Autodesk Fusion 360 part; units mm, degrees
(part 9 of 9)
equation "d2606 = ( ( ( ( layoutGap + keycapSize / 2 + 2 * keyPitch ) - holderStemX ) + ( 2.5 mm ) - 0.5 mm ) + ( 1 mm ) ) - ( ( ( layoutGap + keycapSize / 2 + 2 * keyPitch ) - holderStemX ) + ( 2.5 mm ) - 0.5 mm )"
equation "d2607 = ( ( ( ( ( ( keyRowTwo ) - holderStemY ) - 1.2 mm ) * cos(caseTilt) + ( holderBottomDepth + holderLidGap ) * sin(caseTilt) ) - 1.5 mm ) + ( 3 mm ) ) - ( ( ( ( ( keyRowTwo ) - holderStemY ) - 1.2 mm ) * cos(caseTilt) + ( holderBottomDepth + holderLidGap ) * sin(caseTilt) ) - 1.5 mm )"
equation "d2608 = ( frontHeight + ( ( ( keyRowTwo ) - holderStemY ) - 1.2 mm ) * sin(caseTilt) - ( holderBottomDepth + holderLidGap ) * cos(caseTilt) ) - bottomThickness + 0.5 mm"
equation "d2610 = ( ( ( layoutGap + keycapSize / 2 + 2 * keyPitch ) - holderStemX ) + ( 2.5 mm ) - 0.5 mm ) - 0.1 mm"
equation "d2611 = ( ( ( ( keyRowTwo ) - holderStemY ) - 1.2 mm ) - 2 mm ) + faceOriginV"
equation "d2612 = ( ( ( ( ( layoutGap + keycapSize / 2 + 2 * keyPitch ) - holderStemX ) + ( 2.5 mm ) - 0.5 mm ) - 0.1 mm ) + ( 1.2 mm ) ) - ( ( ( ( layoutGap + keycapSize / 2 + 2 * keyPitch ) - holderStemX ) + ( 2.5 mm ) - 0.5 mm ) - 0.1 mm )"
equation "d2613 = ( ( ( ( ( ( keyRowTwo ) - holderStemY ) - 1.2 mm ) - 2 mm ) + faceOriginV ) + ( 4 mm ) ) - ( ( ( ( ( keyRowTwo ) - holderStemY ) - 1.2 mm ) - 2 mm ) + faceOriginV )"
equation "d2614 = rearHeight"
equation "d2616 = layoutGap + ( displayWidth - oledBoardWidth ) / 2 - oledFitClearance"
equation "d2617 = ( controlCenter - oledBoardLength / 2 - oledFitClearance ) + faceOriginV"
equation "d2618 = ( ( layoutGap + ( displayWidth - oledBoardWidth ) / 2 - oledFitClearance ) + ( oledBoardWidth + 2 * oledFitClearance ) ) - ( layoutGap + ( displayWidth - oledBoardWidth ) / 2 - oledFitClearance )"
equation "d2619 = ( ( ( controlCenter - oledBoardLength / 2 - oledFitClearance ) + faceOriginV ) + ( oledBoardLength + 2 * oledFitClearance ) ) - ( ( controlCenter - oledBoardLength / 2 - oledFitClearance ) + faceOriginV )"
equation "d2620 = -( oledBackDepth + oledFitClearance - shellWall - carrierClearance )"
equation "d2622 = ( 115 mm ) - 11 mm"
equation "d2623 = ( ( keyRowOne ) - 11 mm ) + faceOriginV"
equation "d2624 = ( ( ( 115 mm ) - 11 mm ) + ( 22 mm ) ) - ( ( 115 mm ) - 11 mm )"
equation "d2625 = ( ( ( ( keyRowOne ) - 11 mm ) + faceOriginV ) + ( 22 mm ) ) - ( ( ( keyRowOne ) - 11 mm ) + faceOriginV )"
equation "d2626 = -( carrierThickness )"
equation "d2628 = ( 115 mm ) - switchOpening / 2"
equation "d2629 = ( ( keyRowOne ) - switchOpening / 2 ) + faceOriginV"
equation "d2630 = ( ( ( 115 mm ) - switchOpening / 2 ) + ( switchOpening ) ) - ( ( 115 mm ) - switchOpening / 2 )"
equation "d2631 = ( ( ( ( keyRowOne ) - switchOpening / 2 ) + faceOriginV ) + ( switchOpening ) ) - ( ( ( keyRowOne ) - switchOpening / 2 ) + faceOriginV )"
equation "d2632 = -( carrierThickness + 0.1 mm )"
equation "d2634 = ( 115 mm ) - holderFrameX / 2"
equation "d2635 = ( ( keyRowOne ) - holderFrameY / 2 ) + faceOriginV"
equation "d2636 = ( ( ( 115 mm ) - holderFrameX / 2 ) + ( holderFrameX ) ) - ( ( 115 mm ) - holderFrameX / 2 )"
equation "d2637 = ( ( ( ( keyRowOne ) - holderFrameY / 2 ) + faceOriginV ) + ( holderFrameY ) ) - ( ( ( keyRowOne ) - holderFrameY / 2 ) + faceOriginV )"
equation "d2638 = -( holderBottomDepth + holderHookThickness - shellWall - carrierClearance - carrierThickness )"
equation "d2640 = ( 115 mm ) - holderSwitchVoid / 2"
equation "d2641 = ( ( keyRowOne ) - holderSwitchVoid / 2 ) + faceOriginV"
equation "d2642 = ( ( ( 115 mm ) - holderSwitchVoid / 2 ) + ( holderSwitchVoid ) ) - ( ( 115 mm ) - holderSwitchVoid / 2 )"
equation "d2643 = ( ( ( ( keyRowOne ) - holderSwitchVoid / 2 ) + faceOriginV ) + ( holderSwitchVoid ) ) - ( ( ( keyRowOne ) - holderSwitchVoid / 2 ) + faceOriginV )"
equation "d2644 = -( holderTopDepth - shellWall - carrierClearance - carrierThickness )"
equation "d2646 = ( ( 115 mm ) - holderStemX ) - holderWidth / 2 - holderFit"
equation "d2647 = ( ( ( keyRowOne ) - holderStemY ) - holderLength / 2 - holderFit ) + faceOriginV"
equation "d2648 = ( ( ( ( 115 mm ) - holderStemX ) - holderWidth / 2 - holderFit ) + ( holderWidth + 2 * holderFit ) ) - ( ( ( 115 mm ) - holderStemX ) - holderWidth / 2 - holderFit )"
equation "d2649 = ( ( ( ( ( keyRowOne ) - holderStemY ) - holderLength / 2 - holderFit ) + faceOriginV ) + ( holderLength + 2 * holderFit ) ) - ( ( ( ( keyRowOne ) - holderStemY ) - holderLength / 2 - holderFit ) + faceOriginV )"
equation "d2650 = -( holderHeight + holderHookThickness + 0.2 mm )"
equation "d2652 = ( ( 115 mm ) - holderStemX ) - holderFrameX / 2 - 0.1 mm"
equation "d2653 = ( ( ( ( keyRowOne ) - holderStemY ) + holderSpringY ) - holderSpringWidth / 2 - 0.6 mm ) + faceOriginV"
equation "d2654 = ( ( ( ( 115 mm ) - holderStemX ) - holderFrameX / 2 - 0.1 mm ) + ( holderFrameX / 2 - holderWidth / 2 - holderFit + 0.1 mm ) ) - ( ( ( 115 mm ) - holderStemX ) - holderFrameX / 2 - 0.1 mm )"
equation "d2655 = ( ( ( ( ( ( keyRowOne ) - holderStemY ) + holderSpringY ) - holderSpringWidth / 2 - 0.6 mm ) + faceOriginV ) + ( 0.6 mm ) ) - ( ( ( ( ( keyRowOne ) - holderStemY ) + holderSpringY ) - holderSpringWidth / 2 - 0.6 mm ) + faceOriginV )"
equation "d2656 = -( holderBottomDepth + holderHookThickness - shellWall - carrierClearance - carrierThickness - 1 mm + 0.2 mm )"
equation "d2658 = ( ( 115 mm ) - holderStemX ) - holderFrameX / 2 - 0.1 mm"
equation "d2659 = ( ( ( ( keyRowOne ) - holderStemY ) + holderSpringY ) + holderSpringWidth / 2 ) + faceOriginV"
equation "d2660 = ( ( ( ( 115 mm ) - holderStemX ) - holderFrameX / 2 - 0.1 mm ) + ( holderFrameX / 2 - holderWidth / 2 - holderFit + 0.1 mm ) ) - ( ( ( 115 mm ) - holderStemX ) - holderFrameX / 2 - 0.1 mm )"
equation "d2661 = ( ( ( ( ( ( keyRowOne ) - holderStemY ) + holderSpringY ) + holderSpringWidth / 2 ) + faceOriginV ) + ( 0.6 mm ) ) - ( ( ( ( ( keyRowOne ) - holderStemY ) + holderSpringY ) + holderSpringWidth / 2 ) + faceOriginV )"
equation "d2662 = -( holderBottomDepth + holderHookThickness - shellWall - carrierClearance - carrierThickness - 1 mm + 0.2 mm )"
equation "d2664 = ( ( 115 mm ) - holderStemX ) - holderFrameX / 2 + 0.8 mm"
equation "d2665 = ( ( ( ( keyRowOne ) - holderStemY ) + holderSpringY ) - holderSpringWidth / 2 ) + faceOriginV"
equation "d2666 = ( ( ( ( 115 mm ) - holderStemX ) - holderFrameX / 2 + 0.8 mm ) + ( holderFrameX / 2 - 0.8 mm - holderWidth / 2 - holderFit ) ) - ( ( ( 115 mm ) - holderStemX ) - holderFrameX / 2 + 0.8 mm )"
equation "d2667 = ( ( ( ( ( ( keyRowOne ) - holderStemY ) + holderSpringY ) - holderSpringWidth / 2 ) + faceOriginV ) + ( holderSpringWidth ) ) - ( ( ( ( ( keyRowOne ) - holderStemY ) + holderSpringY ) - holderSpringWidth / 2 ) + faceOriginV )"
equation "d2668 = -( holderHeight + holderHookThickness + 0.2 mm )"
equation "d2670 = ( ( 115 mm ) - holderStemX ) - holderFrameX / 2"
equation "d2671 = ( ( ( ( keyRowOne ) - holderStemY ) + holderSpringY ) - holderSpringWidth / 2 ) + faceOriginV"
equation "d2672 = ( ( ( ( 115 mm ) - holderStemX ) - holderFrameX / 2 ) + ( holderFrameX / 2 - holderWidth / 2 + holderHookOverlap ) ) - ( ( ( 115 mm ) - holderStemX ) - holderFrameX / 2 )"
equation "d2673 = ( ( ( ( ( ( keyRowOne ) - holderStemY ) + holderSpringY ) - holderSpringWidth / 2 ) + faceOriginV ) + ( holderSpringWidth ) ) - ( ( ( ( ( keyRowOne ) - holderStemY ) + holderSpringY ) - holderSpringWidth / 2 ) + faceOriginV )"
equation "d2674 = -( holderHookThickness )"
equation "d2677 = ( ( 115 mm ) - holderStemX ) + holderWidth / 2 + holderFit"
equation "d2678 = ( ( ( ( keyRowOne ) - holderStemY ) + holderSpringY ) - holderSpringWidth / 2 - 0.6 mm ) + faceOriginV"
equation "d2679 = ( ( ( ( 115 mm ) - holderStemX ) + holderWidth / 2 + holderFit ) + ( holderFrameX / 2 - holderWidth / 2 - holderFit + 0.1 mm ) ) - ( ( ( 115 mm ) - holderStemX ) + holderWidth / 2 + holderFit )"
equation "d2680 = ( ( ( ( ( ( keyRowOne ) - holderStemY ) + holderSpringY ) - holderSpringWidth / 2 - 0.6 mm ) + faceOriginV ) + ( 0.6 mm ) ) - ( ( ( ( ( keyRowOne ) - holderStemY ) + holderSpringY ) - holderSpringWidth / 2 - 0.6 mm ) + faceOriginV )"
equation "d2681 = -( holderBottomDepth + holderHookThickness - shellWall - carrierClearance - carrierThickness - 1 mm + 0.2 mm )"
equation "d2683 = ( ( 115 mm ) - holderStemX ) + holderWidth / 2 + holderFit"
equation "d2684 = ( ( ( ( keyRowOne ) - holderStemY ) + holderSpringY ) + holderSpringWidth / 2 ) + faceOriginV"
equation "d2685 = ( ( ( ( 115 mm ) - holderStemX ) + holderWidth / 2 + holderFit ) + ( holderFrameX / 2 - holderWidth / 2 - holderFit + 0.1 mm ) ) - ( ( ( 115 mm ) - holderStemX ) + holderWidth / 2 + holderFit )"
equation "d2686 = ( ( ( ( ( ( keyRowOne ) - holderStemY ) + holderSpringY ) + holderSpringWidth / 2 ) + faceOriginV ) + ( 0.6 mm ) ) - ( ( ( ( ( keyRowOne ) - holderStemY ) + holderSpringY ) + holderSpringWidth / 2 ) + faceOriginV )"
equation "d2687 = -( holderBottomDepth + holderHookThickness - shellWall - carrierClearance - carrierThickness - 1 mm + 0.2 mm )"
equation "d2689 = ( ( 115 mm ) - holderStemX ) + holderWidth / 2 + holderFit"
equation "d2690 = ( ( ( ( keyRowOne ) - holderStemY ) + holderSpringY ) - holderSpringWidth / 2 ) + faceOriginV"
equation "d2691 = ( ( ( ( 115 mm ) - holderStemX ) + holderWidth / 2 + holderFit ) + ( holderFrameX / 2 - 0.8 mm - holderWidth / 2 - holderFit ) ) - ( ( ( 115 mm ) - holderStemX ) + holderWidth / 2 + holderFit )"
equation "d2692 = ( ( ( ( ( ( keyRowOne ) - holderStemY ) + holderSpringY ) - holderSpringWidth / 2 ) + faceOriginV ) + ( holderSpringWidth ) ) - ( ( ( ( ( keyRowOne ) - holderStemY ) + holderSpringY ) - holderSpringWidth / 2 ) + faceOriginV )"
equation "d2693 = -( holderHeight + holderHookThickness + 0.2 mm )"
equation "d2695 = ( ( 115 mm ) - holderStemX ) + holderWidth / 2 - holderHookOverlap"
equation "d2696 = ( ( ( ( keyRowOne ) - holderStemY ) + holderSpringY ) - holderSpringWidth / 2 ) + faceOriginV"
equation "d2697 = ( ( ( ( 115 mm ) - holderStemX ) + holderWidth / 2 - holderHookOverlap ) + ( holderFrameX / 2 - holderWidth / 2 + holderHookOverlap ) ) - ( ( ( 115 mm ) - holderStemX ) + holderWidth / 2 - holderHookOverlap )"
equation "d2698 = ( ( ( ( ( ( keyRowOne ) - holderStemY ) + holderSpringY ) - holderSpringWidth / 2 ) + faceOriginV ) + ( holderSpringWidth ) ) - ( ( ( ( ( keyRowOne ) - holderStemY ) + holderSpringY ) - holderSpringWidth / 2 ) + faceOriginV )"
equation "d2699 = -( holderHookThickness )"
equation "d2702 = ( ( 115 mm ) - holderStemX ) + ( -3 mm ) - 0.5 mm"
equation "d2703 = ( ( ( keyRowOne ) - holderStemY ) + 4 mm ) + faceOriginV"
equation "d2704 = ( ( ( ( 115 mm ) - holderStemX ) + ( -3 mm ) - 0.5 mm ) + ( 1 mm ) ) - ( ( ( 115 mm ) - holderStemX ) + ( -3 mm ) - 0.5 mm )"
equation "d2705 = ( ( ( ( ( keyRowOne ) - holderStemY ) + 4 mm ) + faceOriginV ) + ( holderFrameY / 2 - 4 mm ) ) - ( ( ( ( keyRowOne ) - holderStemY ) + 4 mm ) + faceOriginV )"
equation "d2708 = ( ( 115 mm ) - holderStemX ) + ( 3 mm ) - 0.5 mm"
equation "d2709 = ( ( ( keyRowOne ) - holderStemY ) + 4 mm ) + faceOriginV"
equation "d2710 = ( ( ( ( 115 mm ) - holderStemX ) + ( 3 mm ) - 0.5 mm ) + ( 1 mm ) ) - ( ( ( 115 mm ) - holderStemX ) + ( 3 mm ) - 0.5 mm )"
equation "d2711 = ( ( ( ( ( keyRowOne ) - holderStemY ) + 4 mm ) + faceOriginV ) + ( holderFrameY / 2 - 4 mm ) ) - ( ( ( ( keyRowOne ) - holderStemY ) + 4 mm ) + faceOriginV )"
equation "d2714 = ( ( 115 mm ) - holderStemX ) - holderFrameX / 2 - 0.1 mm"
equation "d2715 = ( ( ( keyRowOne ) - holderStemY ) - 5.1 mm ) + faceOriginV"
equation "d2716 = ( ( ( ( 115 mm ) - holderStemX ) - holderFrameX / 2 - 0.1 mm ) + ( holderFrameX / 2 - holderWidth / 2 + 0.1 mm ) ) - ( ( ( 115 mm ) - holderStemX ) - holderFrameX / 2 - 0.1 mm )"
equation "d2717 = ( ( ( ( ( keyRowOne ) - holderStemY ) - 5.1 mm ) + faceOriginV ) + ( 7.8 mm ) ) - ( ( ( ( keyRowOne ) - holderStemY ) - 5.1 mm ) + faceOriginV )"
equation "d2718 = -( holderHeight + holderHookThickness - 1.2 mm + 0.2 mm )"
equation "d2720 = ( ( 115 mm ) - holderStemX ) + holderWidth / 2"
equation "d2721 = ( ( ( keyRowOne ) - holderStemY ) - 5.1 mm ) + faceOriginV"
equation "d2722 = ( ( ( ( 115 mm ) - holderStemX ) + holderWidth / 2 ) + ( holderFrameX / 2 - holderWidth / 2 + 0.1 mm ) ) - ( ( ( 115 mm ) - holderStemX ) + holderWidth / 2 )"
equation "d2723 = ( ( ( ( ( keyRowOne ) - holderStemY ) - 5.1 mm ) + faceOriginV ) + ( 7.8 mm ) ) - ( ( ( ( keyRowOne ) - holderStemY ) - 5.1 mm ) + faceOriginV )"
equation "d2724 = -( holderHeight + holderHookThickness - 1.2 mm + 0.2 mm )"
equation "d2726 = ( 115 mm ) - 11 mm"
equation "d2727 = ( ( keyRowOne ) * cos(caseTilt) + ( holderBottomDepth + holderLidGap ) * sin(caseTilt) ) - 11 mm"
equation "d2728 = ( ( ( 115 mm ) - 11 mm ) + ( 22 mm ) ) - ( ( 115 mm ) - 11 mm )"
equation "d2729 = ( ( ( ( keyRowOne ) * cos(caseTilt) + ( holderBottomDepth + holderLidGap ) * sin(caseTilt) ) - 11 mm ) + ( 22 mm ) ) - ( ( ( keyRowOne ) * cos(caseTilt) + ( holderBottomDepth + holderLidGap ) * sin(caseTilt) ) - 11 mm )"
equation "d2730 = bottomThickness"
equation "d2732 = ( ( 115 mm ) - holderStemX ) + ( -2.5 mm ) - 1.2 mm"
equation "d2733 = ( ( ( ( keyRowOne ) - holderStemY ) - 1.2 mm ) * cos(caseTilt) + ( holderBottomDepth + holderLidGap ) * sin(caseTilt) ) - 2.5 mm"
equation "d2734 = ( ( ( ( 115 mm ) - holderStemX ) + ( -2.5 mm ) - 1.2 mm ) + ( 2.4 mm ) ) - ( ( ( 115 mm ) - holderStemX ) + ( -2.5 mm ) - 1.2 mm )"
equation "d2735 = ( ( ( ( ( ( keyRowOne ) - holderStemY ) - 1.2 mm ) * cos(caseTilt) + ( holderBottomDepth + holderLidGap ) * sin(caseTilt) ) - 2.5 mm ) + ( 5 mm ) ) - ( ( ( ( ( keyRowOne ) - holderStemY ) - 1.2 mm ) * cos(caseTilt) + ( holderBottomDepth + holderLidGap ) * sin(caseTilt) ) - 2.5 mm )"
equation "d2736 = ( frontHeight + ( ( ( keyRowOne ) - holderStemY ) - 1.2 mm ) * sin(caseTilt) - ( holderBottomDepth + holderLidGap ) * cos(caseTilt) ) - bottomThickness - 2 mm"
equation "d2738 = ( ( 115 mm ) - holderStemX ) + ( -2.5 mm ) - 0.5 mm"
equation "d2739 = ( ( ( ( keyRowOne ) - holderStemY ) - 1.2 mm ) * cos(caseTilt) + ( holderBottomDepth + holderLidGap ) * sin(caseTilt) ) - 1.5 mm"
equation "d2740 = ( ( ( ( 115 mm ) - holderStemX ) + ( -2.5 mm ) - 0.5 mm ) + ( 1 mm ) ) - ( ( ( 115 mm ) - holderStemX ) + ( -2.5 mm ) - 0.5 mm )"
equation "d2741 = ( ( ( ( ( ( keyRowOne ) - holderStemY ) - 1.2 mm ) * cos(caseTilt) + ( holderBottomDepth + holderLidGap ) * sin(caseTilt) ) - 1.5 mm ) + ( 3 mm ) ) - ( ( ( ( ( keyRowOne ) - holderStemY ) - 1.2 mm ) * cos(caseTilt) + ( holderBottomDepth + holderLidGap ) * sin(caseTilt) ) - 1.5 mm )"
equation "d2742 = ( frontHeight + ( ( ( keyRowOne ) - holderStemY ) - 1.2 mm ) * sin(caseTilt) - ( holderBottomDepth + holderLidGap ) * cos(caseTilt) ) - bottomThickness + 0.5 mm"
equation "d2744 = ( ( ( 115 mm ) - holderStemX ) + ( -2.5 mm ) - 0.5 mm ) - 0.1 mm"
equation "d2745 = ( ( ( ( keyRowOne ) - holderStemY ) - 1.2 mm ) - 2 mm ) + faceOriginV"
equation "d2746 = ( ( ( ( ( 115 mm ) - holderStemX ) + ( -2.5 mm ) - 0.5 mm ) - 0.1 mm ) + ( 1.2 mm ) ) - ( ( ( ( 115 mm ) - holderStemX ) + ( -2.5 mm ) - 0.5 mm ) - 0.1 mm )"
equation "d2747 = ( ( ( ( ( ( keyRowOne ) - holderStemY ) - 1.2 mm ) - 2 mm ) + faceOriginV ) + ( 4 mm ) ) - ( ( ( ( ( keyRowOne ) - holderStemY ) - 1.2 mm ) - 2 mm ) + faceOriginV )"
equation "d2748 = rearHeight"
equation "d2750 = ( ( 115 mm ) - holderStemX ) + ( 2.5 mm ) - 1.2 mm"
equation "d2751 = ( ( ( ( keyRowOne ) - holderStemY ) - 1.2 mm ) * cos(caseTilt) + ( holderBottomDepth + holderLidGap ) * sin(caseTilt) ) - 2.5 mm"
equation "d2752 = ( ( ( ( 115 mm ) - holderStemX ) + ( 2.5 mm ) - 1.2 mm ) + ( 2.4 mm ) ) - ( ( ( 115 mm ) - holderStemX ) + ( 2.5 mm ) - 1.2 mm )"
equation "d2753 = ( ( ( ( ( ( keyRowOne ) - holderStemY ) - 1.2 mm ) * cos(caseTilt) + ( holderBottomDepth + holderLidGap ) * sin(caseTilt) ) - 2.5 mm ) + ( 5 mm ) ) - ( ( ( ( ( keyRowOne ) - holderStemY ) - 1.2 mm ) * cos(caseTilt) + ( holderBottomDepth + holderLidGap ) * sin(caseTilt) ) - 2.5 mm )"
equation "d2754 = ( frontHeight + ( ( ( keyRowOne ) - holderStemY ) - 1.2 mm ) * sin(caseTilt) - ( holderBottomDepth + holderLidGap ) * cos(caseTilt) ) - bottomThickness - 2 mm"
equation "d2756 = ( ( 115 mm ) - holderStemX ) + ( 2.5 mm ) - 0.5 mm"
equation "d2757 = ( ( ( ( keyRowOne ) - holderStemY ) - 1.2 mm ) * cos(caseTilt) + ( holderBottomDepth + holderLidGap ) * sin(caseTilt) ) - 1.5 mm"
equation "d2758 = ( ( ( ( 115 mm ) - holderStemX ) + ( 2.5 mm ) - 0.5 mm ) + ( 1 mm ) ) - ( ( ( 115 mm ) - holderStemX ) + ( 2.5 mm ) - 0.5 mm )"
equation "d2759 = ( ( ( ( ( ( keyRowOne ) - holderStemY ) - 1.2 mm ) * cos(caseTilt) + ( holderBottomDepth + holderLidGap ) * sin(caseTilt) ) - 1.5 mm ) + ( 3 mm ) ) - ( ( ( ( ( keyRowOne ) - holderStemY ) - 1.2 mm ) * cos(caseTilt) + ( holderBottomDepth + holderLidGap ) * sin(caseTilt) ) - 1.5 mm )"
equation "d2760 = ( frontHeight + ( ( ( keyRowOne ) - holderStemY ) - 1.2 mm ) * sin(caseTilt) - ( holderBottomDepth + holderLidGap ) * cos(caseTilt) ) - bottomThickness + 0.5 mm"
equation "d2762 = ( ( ( 115 mm ) - holderStemX ) + ( 2.5 mm ) - 0.5 mm ) - 0.1 mm"
equation "d2763 = ( ( ( ( keyRowOne ) - holderStemY ) - 1.2 mm ) - 2 mm ) + faceOriginV"
equation "d2764 = ( ( ( ( ( 115 mm ) - holderStemX ) + ( 2.5 mm ) - 0.5 mm ) - 0.1 mm ) + ( 1.2 mm ) ) - ( ( ( ( 115 mm ) - holderStemX ) + ( 2.5 mm ) - 0.5 mm ) - 0.1 mm )"
equation "d2765 = ( ( ( ( ( ( keyRowOne ) - holderStemY ) - 1.2 mm ) - 2 mm ) + faceOriginV ) + ( 4 mm ) ) - ( ( ( ( ( keyRowOne ) - holderStemY ) - 1.2 mm ) - 2 mm ) + faceOriginV )"
equation "d2766 = rearHeight"
equation "compactTrialX = 145 mm" comment "Separate V2 coupon center"
equation "compactGuideClearance = 0.2 mm" comment "Radial clearance in STL 0.95 mm side notches"
equation "compactGuideHeight = 3 mm" comment "Guide within 3.2 mm notched region"
equation "compactStopWidth = 1.8 mm" comment "Wider upper stops for physical test"
equation "compactWireDiameter = 1.5 mm" comment "Provisional through-wall wire routing diameter"
equation "d2773 = compactTrialX - 11 mm"
equation "d2774 = ( keyRowOne - 11 mm ) + faceOriginV"
equation "d2775 = ( ( compactTrialX - 11 mm ) + ( 22 mm ) ) - ( compactTrialX - 11 mm )"
equation "d2776 = ( ( ( keyRowOne - 11 mm ) + faceOriginV ) + ( 22 mm ) ) - ( ( keyRowOne - 11 mm ) + faceOriginV )"
equation "d2777 = -( carrierThickness )"
equation "d2779 = compactTrialX - switchOpening / 2"
equation "d2780 = ( keyRowOne - switchOpening / 2 ) + faceOriginV"
equation "d2781 = ( ( compactTrialX - switchOpening / 2 ) + ( switchOpening ) ) - ( compactTrialX - switchOpening / 2 )"
equation "d2782 = ( ( ( keyRowOne - switchOpening / 2 ) + faceOriginV ) + ( switchOpening ) ) - ( ( keyRowOne - switchOpening / 2 ) + faceOriginV )"
equation "d2783 = -( carrierThickness + 0.1 mm )"
equation "d2785 = compactTrialX - holderFrameX / 2"
equation "d2786 = ( keyRowOne - holderFrameY / 2 ) + faceOriginV"
equation "d2787 = ( ( compactTrialX - holderFrameX / 2 ) + ( holderFrameX ) ) - ( compactTrialX - holderFrameX / 2 )"
equation "d2788 = ( ( ( keyRowOne - holderFrameY / 2 ) + faceOriginV ) + ( holderFrameY ) ) - ( ( keyRowOne - holderFrameY / 2 ) + faceOriginV )"
equation "d2789 = -( holderBottomDepth - shellWall - carrierClearance - carrierThickness )"
equation "d2791 = compactTrialX - holderSwitchVoid / 2"
equation "d2792 = ( keyRowOne - holderSwitchVoid / 2 ) + faceOriginV"
equation "d2793 = ( ( compactTrialX - holderSwitchVoid / 2 ) + ( holderSwitchVoid ) ) - ( compactTrialX - holderSwitchVoid / 2 )"
equation "d2794 = ( ( ( keyRowOne - holderSwitchVoid / 2 ) + faceOriginV ) + ( holderSwitchVoid ) ) - ( ( keyRowOne - holderSwitchVoid / 2 ) + faceOriginV )"
equation "d2795 = -( holderTopDepth - shellWall - carrierClearance - carrierThickness )"
equation "d2797 = compactTrialX - 5.42601681 mm - holderFit"
equation "d2798 = ( keyRowOne - 6.37220383 mm - holderFit ) + faceOriginV"
equation "d2799 = ( ( compactTrialX - 5.42601681 mm - holderFit ) + ( 11.03147984 mm + 2 * holderFit ) ) - ( compactTrialX - 5.42601681 mm - holderFit )"
equation "d2800 = ( ( ( keyRowOne - 6.37220383 mm - holderFit ) + faceOriginV ) + ( 9.74910235 mm + 2 * holderFit ) ) - ( ( keyRowOne - 6.37220383 mm - holderFit ) + faceOriginV )"
equation "d2801 = -( holderHeight + 0.1 mm )"
equation "d2803 = compactTrialX + ( -1 * 3 mm ) - compactStopWidth / 2"
equation "d2804 = ( keyRowOne + 2.6 mm ) + faceOriginV"
equation "d2805 = ( ( compactTrialX + ( -1 * 3 mm ) - compactStopWidth / 2 ) + ( compactStopWidth ) ) - ( compactTrialX + ( -1 * 3 mm ) - compactStopWidth / 2 )"
equation "d2806 = ( ( ( keyRowOne + 2.6 mm ) + faceOriginV ) + ( holderFrameY / 2 - 2.6 mm ) ) - ( ( keyRowOne + 2.6 mm ) + faceOriginV )"
equation "d2809 = compactTrialX - holderFrameX / 2"
equation "d2810 = ( keyRowOne - 0.35 mm ) + faceOriginV"
equation "d2811 = ( ( compactTrialX - holderFrameX / 2 ) + ( holderFrameX / 2 - 4.8 mm ) ) - ( compactTrialX - holderFrameX / 2 )"
equation "d2812 = ( ( ( keyRowOne - 0.35 mm ) + faceOriginV ) + ( 0.7 mm ) ) - ( ( keyRowOne - 0.35 mm ) + faceOriginV )"
equation "d2813 = compactGuideHeight"
equation "d2815 = compactTrialX + ( -1 * 4.8 mm )"
equation "d2816 = ( keyRowOne ) + faceOriginV"
equation "d2817 = 2 * ( 0.95 mm - compactGuideClearance )"
equation "d2818 = compactGuideHeight"
equation "d2820 = compactTrialX + ( 1 * 3 mm ) - compactStopWidth / 2"
equation "d2821 = ( keyRowOne + 2.6 mm ) + faceOriginV"
equation "d2822 = ( ( compactTrialX + ( 1 * 3 mm ) - compactStopWidth / 2 ) + ( compactStopWidth ) ) - ( compactTrialX + ( 1 * 3 mm ) - compactStopWidth / 2 )"
equation "d2823 = ( ( ( keyRowOne + 2.6 mm ) + faceOriginV ) + ( holderFrameY / 2 - 2.6 mm ) ) - ( ( keyRowOne + 2.6 mm ) + faceOriginV )"
equation "d2826 = compactTrialX + 4.8 mm"
equation "d2827 = ( keyRowOne - 0.35 mm ) + faceOriginV"
equation "d2828 = ( ( compactTrialX + 4.8 mm ) + ( holderFrameX / 2 - 4.8 mm ) ) - ( compactTrialX + 4.8 mm )"
equation "d2829 = ( ( ( keyRowOne - 0.35 mm ) + faceOriginV ) + ( 0.7 mm ) ) - ( ( keyRowOne - 0.35 mm ) + faceOriginV )"
equation "d2830 = compactGuideHeight"
equation "d2832 = compactTrialX + ( 1 * 4.8 mm )"
equation "d2833 = ( keyRowOne ) + faceOriginV"
equation "d2834 = 2 * ( 0.95 mm - compactGuideClearance )"
equation "d2835 = compactGuideHeight"
equation "d2837 = compactTrialX - 10 mm"
equation "d2839 = -( -1.7062782001271268 cm )"
equation "d2841 = compactWireDiameter"
equation "d2844 = -( -1.68700663682872 cm )"
equation "d2846 = compactWireDiameter"
equation "d2849 = -( -1.9961218786424535 cm )"
equation "d2851 = compactWireDiameter"
equation "d2854 = caseTilt"
equation "d2856 = 1 * ( keyRowOne + 10 mm + frontHeight * sin(caseTilt) )"
equation "d2859 = -( -1.7982695244660625 cm )"
equation "d2860 = compactWireDiameter"
equation "d2861 = -( 20 mm )"
equation "compactV3TrialX = 175 mm" comment "Separate V3 coupon center"
equation "compactV3Shift = 3 mm" comment "Move holder toward switch based on pin-tip measurement"
equation "compactV3TopDepth = holderTopDepth - compactV3Shift" comment "Local trial depth; preserve main carrier"
equation "compactV3BottomDepth = compactV3TopDepth + holderHeight" comment "New holder bottom datum"
equation "compactV3GuideClearance = 0.2 mm" comment "Radial clearance in STL 0.95 mm side notches"
equation "compactV3GuideHeight = 3 mm" comment "Guide within 3.2 mm notched region"
equation "compactV3StopWidth = 1.8 mm" comment "Wider upper stops for physical test"
equation "compactV3WireDiameter = 1.5 mm" comment "Provisional through-wall wire routing diameter"
equation "d2871 = -compactV3TopDepth"
equation "d2873 = -compactV3BottomDepth"
equation "d2875 = compactV3TrialX - 11 mm"
equation "d2876 = ( keyRowOne - 11 mm ) + faceOriginV"
equation "d2877 = ( ( compactV3TrialX - 11 mm ) + ( 22 mm ) ) - ( compactV3TrialX - 11 mm )"
equation "d2878 = ( ( ( keyRowOne - 11 mm ) + faceOriginV ) + ( 22 mm ) ) - ( ( keyRowOne - 11 mm ) + faceOriginV )"
equation "d2879 = -( carrierThickness )"
equation "d2881 = compactV3TrialX - switchOpening / 2"
equation "d2882 = ( keyRowOne - switchOpening / 2 ) + faceOriginV"
equation "d2883 = ( ( compactV3TrialX - switchOpening / 2 ) + ( switchOpening ) ) - ( compactV3TrialX - switchOpening / 2 )"
equation "d2884 = ( ( ( keyRowOne - switchOpening / 2 ) + faceOriginV ) + ( switchOpening ) ) - ( ( keyRowOne - switchOpening / 2 ) + faceOriginV )"
equation "d2885 = -( carrierThickness + 0.1 mm )"
equation "d2887 = compactV3TrialX - holderFrameX / 2"
equation "d2888 = ( keyRowOne - holderFrameY / 2 ) + faceOriginV"
equation "d2889 = ( ( compactV3TrialX - holderFrameX / 2 ) + ( holderFrameX ) ) - ( compactV3TrialX - holderFrameX / 2 )"
equation "d2890 = ( ( ( keyRowOne - holderFrameY / 2 ) + faceOriginV ) + ( holderFrameY ) ) - ( ( keyRowOne - holderFrameY / 2 ) + faceOriginV )"
equation "d2891 = -( compactV3BottomDepth - shellWall - carrierClearance - carrierThickness )"
equation "d2893 = compactV3TrialX - holderSwitchVoid / 2"
equation "d2894 = ( keyRowOne - holderSwitchVoid / 2 ) + faceOriginV"
equation "d2895 = ( ( compactV3TrialX - holderSwitchVoid / 2 ) + ( holderSwitchVoid ) ) - ( compactV3TrialX - holderSwitchVoid / 2 )"
equation "d2896 = ( ( ( keyRowOne - holderSwitchVoid / 2 ) + faceOriginV ) + ( holderSwitchVoid ) ) - ( ( keyRowOne - holderSwitchVoid / 2 ) + faceOriginV )"
equation "d2897 = -( compactV3TopDepth - shellWall - carrierClearance - carrierThickness )"
equation "d2899 = compactV3TrialX - 5.42601681 mm - holderFit"
equation "d2900 = ( keyRowOne - 6.37220383 mm - holderFit ) + faceOriginV"
equation "d2901 = ( ( compactV3TrialX - 5.42601681 mm - holderFit ) + ( 11.03147984 mm + 2 * holderFit ) ) - ( compactV3TrialX - 5.42601681 mm - holderFit )"
equation "d2902 = ( ( ( keyRowOne - 6.37220383 mm - holderFit ) + faceOriginV ) + ( 9.74910235 mm + 2 * holderFit ) ) - ( ( keyRowOne - 6.37220383 mm - holderFit ) + faceOriginV )"
equation "d2903 = -( holderHeight + 0.1 mm )"
equation "d2905 = compactV3TrialX + ( -1 * 3 mm ) - compactV3StopWidth / 2"
equation "d2906 = ( keyRowOne + 2.6 mm ) + faceOriginV"
equation "d2907 = ( ( compactV3TrialX + ( -1 * 3 mm ) - compactV3StopWidth / 2 ) + ( compactV3StopWidth ) ) - ( compactV3TrialX + ( -1 * 3 mm ) - compactV3StopWidth / 2 )"
equation "d2908 = ( ( ( keyRowOne + 2.6 mm ) + faceOriginV ) + ( holderFrameY / 2 - 2.6 mm ) ) - ( ( keyRowOne + 2.6 mm ) + faceOriginV )"
equation "d2911 = compactV3TrialX - holderFrameX / 2"
equation "d2912 = ( keyRowOne - 0.35 mm ) + faceOriginV"
equation "d2913 = ( ( compactV3TrialX - holderFrameX / 2 ) + ( holderFrameX / 2 - 4.8 mm ) ) - ( compactV3TrialX - holderFrameX / 2 )"
equation "d2914 = ( ( ( keyRowOne - 0.35 mm ) + faceOriginV ) + ( 0.7 mm ) ) - ( ( keyRowOne - 0.35 mm ) + faceOriginV )"
equation "d2915 = compactV3GuideHeight"
equation "d2917 = compactV3TrialX + ( -1 * 4.8 mm )"
equation "d2918 = ( keyRowOne ) + faceOriginV"
equation "d2919 = 2 * ( 0.95 mm - compactV3GuideClearance )"
equation "d2920 = compactV3GuideHeight"
equation "d2922 = compactV3TrialX + ( 1 * 3 mm ) - compactV3StopWidth / 2"
equation "d2923 = ( keyRowOne + 2.6 mm ) + faceOriginV"
equation "d2924 = ( ( compactV3TrialX + ( 1 * 3 mm ) - compactV3StopWidth / 2 ) + ( compactV3StopWidth ) ) - ( compactV3TrialX + ( 1 * 3 mm ) - compactV3StopWidth / 2 )"
equation "d2925 = ( ( ( keyRowOne + 2.6 mm ) + faceOriginV ) + ( holderFrameY / 2 - 2.6 mm ) ) - ( ( keyRowOne + 2.6 mm ) + faceOriginV )"
equation "d2928 = compactV3TrialX + 4.8 mm"
equation "d2929 = ( keyRowOne - 0.35 mm ) + faceOriginV"
equation "d2930 = ( ( compactV3TrialX + 4.8 mm ) + ( holderFrameX / 2 - 4.8 mm ) ) - ( compactV3TrialX + 4.8 mm )"
equation "d2931 = ( ( ( keyRowOne - 0.35 mm ) + faceOriginV ) + ( 0.7 mm ) ) - ( ( keyRowOne - 0.35 mm ) + faceOriginV )"
equation "d2932 = compactV3GuideHeight"
equation "d2934 = compactV3TrialX + ( 1 * 4.8 mm )"
equation "d2935 = ( keyRowOne ) + faceOriginV"
equation "d2936 = 2 * ( 0.95 mm - compactV3GuideClearance )"
equation "d2937 = compactV3GuideHeight"
equation "d2939 = compactV3TrialX - 10 mm"
equation "d2941 = -( -2.0051366095546506 cm )"
equation "d2943 = compactV3WireDiameter"
equation "d2946 = -( -1.9858650462562437 cm )"
equation "d2948 = compactV3WireDiameter"
equation "d2951 = -( -2.294980288069977 cm )"
equation "d2953 = compactV3WireDiameter"
equation "d2956 = caseTilt"
equation "d2958 = 1 * ( keyRowOne + 10 mm + frontHeight * sin(caseTilt) )"
equation "d2961 = -( -2.098269524466062 cm )"
equation "d2962 = compactV3WireDiameter"
equation "d2963 = -( 20 mm )"
equation "d2965 = -( compactV3BottomDepth + holderLidGap )"
equation "d2967 = compactV3TrialX - 11 mm"
equation "d2968 = ( ( keyRowOne ) * cos(caseTilt) + ( compactV3BottomDepth + holderLidGap ) * sin(caseTilt) ) - 11 mm"
equation "d2969 = ( ( compactV3TrialX - 11 mm ) + ( 22 mm ) ) - ( compactV3TrialX - 11 mm )"
equation "d2970 = ( ( ( ( keyRowOne ) * cos(caseTilt) + ( compactV3BottomDepth + holderLidGap ) * sin(caseTilt) ) - 11 mm ) + ( 22 mm ) ) - ( ( ( keyRowOne ) * cos(caseTilt) + ( compactV3BottomDepth + holderLidGap ) * sin(caseTilt) ) - 11 mm )"
equation "d2971 = bottomThickness"
equation "d2973 = ( ( compactV3TrialX ) - holderStemX ) + ( -2.5 mm ) - 1.2 mm"
equation "d2974 = ( ( ( ( keyRowOne ) - holderStemY ) - 1.2 mm ) * cos(caseTilt) + ( compactV3BottomDepth + holderLidGap ) * sin(caseTilt) ) - 2.5 mm"
equation "d2975 = ( ( ( ( compactV3TrialX ) - holderStemX ) + ( -2.5 mm ) - 1.2 mm ) + ( 2.4 mm ) ) - ( ( ( compactV3TrialX ) - holderStemX ) + ( -2.5 mm ) - 1.2 mm )"
equation "d2976 = ( ( ( ( ( ( keyRowOne ) - holderStemY ) - 1.2 mm ) * cos(caseTilt) + ( compactV3BottomDepth + holderLidGap ) * sin(caseTilt) ) - 2.5 mm ) + ( 5 mm ) ) - ( ( ( ( ( keyRowOne ) - holderStemY ) - 1.2 mm ) * cos(caseTilt) + ( compactV3BottomDepth + holderLidGap ) * sin(caseTilt) ) - 2.5 mm )"
equation "d2977 = ( frontHeight + ( ( ( keyRowOne ) - holderStemY ) - 1.2 mm ) * sin(caseTilt) - ( compactV3BottomDepth + holderLidGap ) * cos(caseTilt) ) - bottomThickness - 2 mm"
equation "d2979 = ( ( compactV3TrialX ) - holderStemX ) + ( -2.5 mm ) - 0.5 mm"
equation "d2980 = ( ( ( ( keyRowOne ) - holderStemY ) - 1.2 mm ) * cos(caseTilt) + ( compactV3BottomDepth + holderLidGap ) * sin(caseTilt) ) - 1.5 mm"
equation "d2981 = ( ( ( ( compactV3TrialX ) - holderStemX ) + ( -2.5 mm ) - 0.5 mm ) + ( 1 mm ) ) - ( ( ( compactV3TrialX ) - holderStemX ) + ( -2.5 mm ) - 0.5 mm )"
equation "d2982 = ( ( ( ( ( ( keyRowOne ) - holderStemY ) - 1.2 mm ) * cos(caseTilt) + ( compactV3BottomDepth + holderLidGap ) * sin(caseTilt) ) - 1.5 mm ) + ( 3 mm ) ) - ( ( ( ( ( keyRowOne ) - holderStemY ) - 1.2 mm ) * cos(caseTilt) + ( compactV3BottomDepth + holderLidGap ) * sin(caseTilt) ) - 1.5 mm )"
equation "d2983 = ( frontHeight + ( ( ( keyRowOne ) - holderStemY ) - 1.2 mm ) * sin(caseTilt) - ( compactV3BottomDepth + holderLidGap ) * cos(caseTilt) ) - bottomThickness + 0.5 mm"
equation "d2985 = ( ( ( compactV3TrialX ) - holderStemX ) + ( -2.5 mm ) - 0.5 mm ) - 0.1 mm"
equation "d2986 = ( ( ( ( keyRowOne ) - holderStemY ) - 1.2 mm ) - 2 mm ) + faceOriginV"
equation "d2987 = ( ( ( ( ( compactV3TrialX ) - holderStemX ) + ( -2.5 mm ) - 0.5 mm ) - 0.1 mm ) + ( 1.2 mm ) ) - ( ( ( ( compactV3TrialX ) - holderStemX ) + ( -2.5 mm ) - 0.5 mm ) - 0.1 mm )"
equation "d2988 = ( ( ( ( ( ( keyRowOne ) - holderStemY ) - 1.2 mm ) - 2 mm ) + faceOriginV ) + ( 4 mm ) ) - ( ( ( ( ( keyRowOne ) - holderStemY ) - 1.2 mm ) - 2 mm ) + faceOriginV )"
equation "d2989 = rearHeight"
equation "d2991 = ( ( compactV3TrialX ) - holderStemX ) + ( 2.5 mm ) - 1.2 mm"
equation "d2992 = ( ( ( ( keyRowOne ) - holderStemY ) - 1.2 mm ) * cos(caseTilt) + ( compactV3BottomDepth + holderLidGap ) * sin(caseTilt) ) - 2.5 mm"
equation "d2993 = ( ( ( ( compactV3TrialX ) - holderStemX ) + ( 2.5 mm ) - 1.2 mm ) + ( 2.4 mm ) ) - ( ( ( compactV3TrialX ) - holderStemX ) + ( 2.5 mm ) - 1.2 mm )"
equation "d2994 = ( ( ( ( ( ( keyRowOne ) - holderStemY ) - 1.2 mm ) * cos(caseTilt) + ( compactV3BottomDepth + holderLidGap ) * sin(caseTilt) ) - 2.5 mm ) + ( 5 mm ) ) - ( ( ( ( ( keyRowOne ) - holderStemY ) - 1.2 mm ) * cos(caseTilt) + ( compactV3BottomDepth + holderLidGap ) * sin(caseTilt) ) - 2.5 mm )"
equation "d2995 = ( frontHeight + ( ( ( keyRowOne ) - holderStemY ) - 1.2 mm ) * sin(caseTilt) - ( compactV3BottomDepth + holderLidGap ) * cos(caseTilt) ) - bottomThickness - 2 mm"
equation "d2997 = ( ( compactV3TrialX ) - holderStemX ) + ( 2.5 mm ) - 0.5 mm"
equation "d2998 = ( ( ( ( keyRowOne ) - holderStemY ) - 1.2 mm ) * cos(caseTilt) + ( compactV3BottomDepth + holderLidGap ) * sin(caseTilt) ) - 1.5 mm"
equation "d2999 = ( ( ( ( compactV3TrialX ) - holderStemX ) + ( 2.5 mm ) - 0.5 mm ) + ( 1 mm ) ) - ( ( ( compactV3TrialX ) - holderStemX ) + ( 2.5 mm ) - 0.5 mm )"
equation "d3000 = ( ( ( ( ( ( keyRowOne ) - holderStemY ) - 1.2 mm ) * cos(caseTilt) + ( compactV3BottomDepth + holderLidGap ) * sin(caseTilt) ) - 1.5 mm ) + ( 3 mm ) ) - ( ( ( ( ( keyRowOne ) - holderStemY ) - 1.2 mm ) * cos(caseTilt) + ( compactV3BottomDepth + holderLidGap ) * sin(caseTilt) ) - 1.5 mm )"
equation "d3001 = ( frontHeight + ( ( ( keyRowOne ) - holderStemY ) - 1.2 mm ) * sin(caseTilt) - ( compactV3BottomDepth + holderLidGap ) * cos(caseTilt) ) - bottomThickness + 0.5 mm"
equation "d3003 = ( ( ( compactV3TrialX ) - holderStemX ) + ( 2.5 mm ) - 0.5 mm ) - 0.1 mm"
equation "d3004 = ( ( ( ( keyRowOne ) - holderStemY ) - 1.2 mm ) - 2 mm ) + faceOriginV"
equation "d3005 = ( ( ( ( ( compactV3TrialX ) - holderStemX ) + ( 2.5 mm ) - 0.5 mm ) - 0.1 mm ) + ( 1.2 mm ) ) - ( ( ( ( compactV3TrialX ) - holderStemX ) + ( 2.5 mm ) - 0.5 mm ) - 0.1 mm )"
equation "d3006 = ( ( ( ( ( ( keyRowOne ) - holderStemY ) - 1.2 mm ) - 2 mm ) + faceOriginV ) + ( 4 mm ) ) - ( ( ( ( ( keyRowOne ) - holderStemY ) - 1.2 mm ) - 2 mm ) + faceOriginV )"
equation "d3007 = rearHeight"
named bodies: "UpperShell_Draft", "MiddleCarrier_Draft", "BottomCover_Draft", "Diffuser_Draft", "SwitchFitCoupon_Trial", "LidSupportCoupon_Trial", "SwitchFitCoupon_Compact_V2", "SwitchFitCoupon_Compact_V3", "LidSupportCoupon_Compact_V3"
